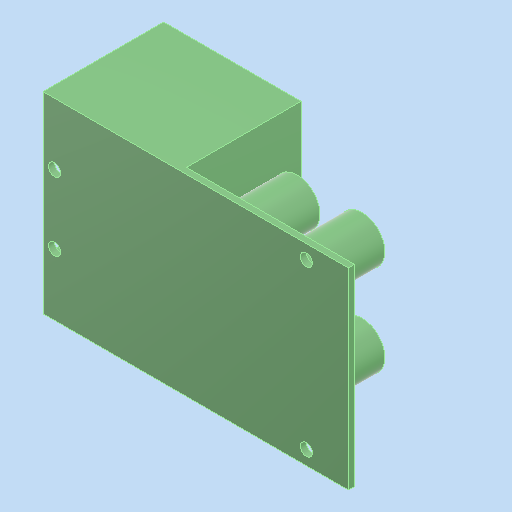
# Autodesk Inventor part: 12V_DCDC
Saved by Autodesk Inventor 2025.3 (Build 293356030, 356C)
## iProperties
Created: 2025-08-01
Part Number: 12V_DCDC
Material: 一般
Document SubType Name: Modeling
Designer: ibuki_ono
Density: 1 g/cm^3
Appearance: 滑らか - 濃い深緑
Author: ibuki_ono
Autodesk Inventor part; units mm, degrees
ref_plane "YZ Plane" through (0, 0, 0) normal (1, 0, 0) x (0, 1, 0)
ref_plane "XZ Plane" through (0, 0, 0) normal (0, 1, 0) x (-1, 0, 0)
ref_plane "XY Plane" through (0, 0, 0) normal (0, 0, 1) x (1, 0, 0)
sketch "スケッチ1" plane through (0, 0, 0) normal (0, 0, 1) x (1, 0, 0)
  line L0 (-40, -25.2) -> (40, -25.2)
  line L1 (40, -25.2) -> (40, 25.2)
  line L2 (40, 25.2) -> (-40, 25.2)
  line L3 (-40, 25.2) -> (-40, -25.2)
  line L4 (-40, -25.2) -> (40, 25.2) construction
  line L5 (40, -25.2) -> (-40, 25.2) construction
  point P0 (0, 0)
  dimension "d0" = 80
  dimension "d1" = 50.4
  constraints: 12 end point, 2 midpoint, 2 parallel, 1 horizontal, 1 perpendicular
  measures "d0" distance of L2.end L1.end
  measures "d1" distance of L1.end L0.end
extrude "押し出し1" add sketch "スケッチ1" along normal mid plane 1.6
sketch "スケッチ2" plane through (0, 0, 0.8) normal (0, 0, 1) x (1, 0, 0)
  line L0 (40, -25.2) -> (40, 25.2) projected
  line L1 (40, 25.2) -> (-40, 25.2) projected
  line L2 (-40, -25.2) -> (40, -25.2) projected
  line L3 (-40, 25.2) -> (-40, -25.2) projected
  point P0 (0, 0)
  point P1 (-37, 9)
  point P2 (-37, -9)
  point P3 (29, 21.5)
  point P4 (29, -21.5)
  dimension "d4" = 11
  dimension "d5" = 11
  dimension "d6" = 3.7
  dimension "d7" = 3.7
  dimension "d8" = 3
  dimension "d9" = 3
  dimension "d10" = 16.2
  dimension "d11" = 16.2
  measures "d4" distance from line of L0 point (29, 21.5)
  measures "d5" distance from line of L0 point (29, -21.5)
  measures "d6" distance from line of L1 point (29, 21.5)
  measures "d7" distance from line of L2 point (29, -21.5)
  measures "d8" distance from line of L3 point (-37, 9)
  measures "d9" distance from line of L3 point (-37, -9)
  measures "d10" distance from line of L2 point (-37, -9)
  measures "d11" distance from line of L1 point (-37, 9)
hole "穴1" at (-37, 9, 0.8) at (-37, -9, 0.8) at (29, 21.5, 0.8) at (29, -21.5, 0.8) direction (0, 0, -1) diameter 3.2 end through all
sketch "スケッチ3" plane through (0, 0, -0.8) normal (0, 0, -1) x (-1, 0, 0)
  line L0 (-40, -25.2) -> (40, -25.2) projected
  line L1 (40, -25.2) -> (40, 25.2) projected
  line L2 (40, 25.2) -> (-40, 25.2) projected
  line L3 (4, -25.2) -> (4, 25.2)
  line L4 (40, 12) -> (34, 12)
  line L5 (34, 12) -> (34, -12)
  line L6 (34, -12) -> (40, -12)
  point P0 (0, 0)
  point P1 (34, 0)
  point P2 (40, 0)
  point P3 (40, 0)
  dimension "d19" = 36
  dimension "d20" = 6
  dimension "d21" = 12
  constraints: 8 end point, 4 point on line, 3 midpoint, 3 perpendicular, 1 horizontal, 1 horizontal alignment
  measures "d19" distance between parallel lines of L1 L3
  measures "d20" distance between parallel lines of L1 L5
  measures "d21" distance from line of point (40, 0) L6
extrude "押し出し2" add sketch "スケッチ3" along normal blind 30 contours L3 L2 L1 L4 L5 L6 L0
sketch "スケッチ4" plane through (0, 0, -0.8) normal (0, 0, -1) x (-1, 0, 0)
  circle A0 centre (-5, -12) radius 6
  circle A1 centre (-22, -12) radius 6
  circle A2 centre (-5, 12) radius 6
  circle A3 centre (-22, 12) radius 6
  line L0 (-40, 25.2) -> (-40, -25.2) projected
  point P0 (0, 0)
  point P1 (-40, 0)
  point P2 (-40, 0)
  point P3 (-40, 0)
  point P4 (-40, 0)
  dimension "d24" = 12
  dimension "d25" = 12
  dimension "d26" = 12
  dimension "d27" = 12
  dimension "d28" = 35
  dimension "d29" = 35
  dimension "d30" = 18
  dimension "d31" = 18
  dimension "d32" = 12
  dimension "d33" = 12
  dimension "d34" = 12
  dimension "d35" = 12
  constraints: 4 centre point, 4 midpoint
  measures "d24" diameter of A0
  measures "d25" diameter of A1
  measures "d26" diameter of A2
  measures "d27" diameter of A3
  measures "d28" distance from line of L0 A0.centre
  measures "d29" distance from line of L0 A2.centre
  measures "d30" distance from line of L0 A1.centre
  measures "d31" distance from line of L0 A3.centre
  measures "d32" vertical distance of point (-40, 0) A1.centre
  measures "d33" vertical distance of point (-40, 0) A0.centre
  measures "d34" vertical distance of point (-40, 0) A3.centre
  measures "d35" vertical distance of point (-40, 0) A2.centre
extrude "押し出し3" add sketch "スケッチ4" along normal blind 20
equation "\"d5\" = d4"
equation "\"d7\" = d6"
equation "\"d9\" = d8"
equation "\"d11\" = d10"
equation "\"d24\" = d26"
equation "\"d25\" = d27"
equation "\"d29\" = d28"
equation "\"d31\" = d30"
equation "\"d33\" = d32"
equation "\"d34\" = d32"
equation "\"d35\" = d33"
